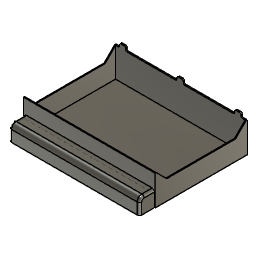
Medium_Drawer_PRINT (Autodesk Fusion 360 design; units mm, degrees)
Autodesk Fusion 360 part; units mm, degrees
sketch "Sketch1" plane through (0, 0, 0) normal (0, 0, 1) x (1, 0, 0)
  line L0 (0, 0) -> (113.9, 0)
  line L1 (113.9, 0) -> (113.9, 80)
  line L2 (113.9, 80) -> (0, 80)
  line L3 (0, 80) -> (0, 0)
  dimension "d1" = 113.9
  dimension "d2" = 80
  constraint horizontal L0
  constraint vertical L1
  constraint horizontal L2
  constraint vertical L3
  constraint coincident L0.start L3.end
  measures "d1" distance of L0.start L0.end
  measures "d2" distance of L0.end L1.end
extrude "Extrude1" add sketch "Sketch1" along normal blind 26.2
shell "Shell1" thickness 0.8 removed faces 1 at (37.9667, 53.3333, 26.2)
ref_plane "WorkPlane1" through (95.5, 40, 13.1) normal (1, 0, 0) x (0, 1, 0)
sketch "Sketch3" plane through (0, 80, 0) normal (0, 1, 0) x (-1, 0, 0)
  line L0 (-113.9, 0) -> (0, 0)
  line L1 (0, 0) -> (0, 26.2)
  line L2 (0, 26.2) -> (-113.9, 26.2)
  line L3 (-113.9, 26.2) -> (-113.9, 0)
  line L4 (-56.95, 26.2) -> (-56.95, 0) construction
  line L5 (-109.65, 27.45) -> (-109.65, 28.45)
  line L6 (-108.4, 29.7) -> (-105.4, 29.7)
  line L7 (-104.15, 28.45) -> (-104.15, 27.45)
  line L8 (-110.9, 26.2) -> (-102.9, 26.2)
  arc A0 (-110.9, 26.2) -> (-109.65, 27.45) centre (-110.9, 27.45) ccw
  arc A1 (-108.4, 29.7) -> (-109.65, 28.45) centre (-108.4, 28.45) ccw
  arc A2 (-104.15, 28.45) -> (-105.4, 29.7) centre (-105.4, 28.45) ccw
  arc A3 (-104.15, 27.45) -> (-102.9, 26.2) centre (-102.9, 27.45) ccw
  arc A4 (-4.25, 28.45) -> (-5.5, 29.7) centre (-5.5, 28.45) ccw
  line L9 (-5.5, 29.7) -> (-8.5, 29.7)
  arc A5 (-11, 26.2) -> (-9.75, 27.45) centre (-11, 27.45) ccw
  arc A6 (-4.25, 27.45) -> (-3, 26.2) centre (-3, 27.45) ccw
  line L10 (-4.25, 27.45) -> (-4.25, 28.45)
  line L11 (-3, 26.2) -> (-11, 26.2)
  arc A7 (-8.5, 29.7) -> (-9.75, 28.45) centre (-8.5, 28.45) ccw
  line L12 (-9.75, 28.45) -> (-9.75, 27.45)
  line L13 (-58.25, 29.7) -> (-55.25, 29.7)
  arc A8 (-58.25, 29.7) -> (-59.5, 28.45) centre (-58.25, 28.45) ccw
  line L14 (-59.5, 27.45) -> (-59.5, 28.45)
  arc A9 (-60.75, 26.2) -> (-59.5, 27.45) centre (-60.75, 27.45) ccw
  arc A10 (-54, 27.45) -> (-52.75, 26.2) centre (-52.75, 27.45) ccw
  line L15 (-60.75, 26.2) -> (-52.75, 26.2)
  line L16 (-54, 28.45) -> (-54, 27.45)
  arc A11 (-54, 28.45) -> (-55.25, 29.7) centre (-55.25, 28.45) ccw
  point P0 (-106.9, 29.7)
  point P1 (-7, 29.7)
  dimension "d18" = 7
  dimension "d19" = 3.5
  dimension "d20" = 5.5
  dimension "d21" = 1.25
  dimension "d62" = 3.5
  dimension "d63" = 5.5
  dimension "d64" = 1.25
  dimension "d65" = 114.3
  dimension "d66" = 44.65
  dimension "d67" = 44.8
  dimension "d68" = 8
  dimension "d69" = 1.25
  dimension "d70" = 3
  dimension "d71" = 1.25
  dimension "d72" = 1.25
  dimension "d73" = 1.25
  dimension "d74" = 3.5
  constraint midpoint L2 L4.start
  constraint perpendicular L2 L4
  constraint coincident L0 L4.end
  constraint horizontal L6
  constraint tangent L6 A1
  constraint tangent L5 A1
  constraint tangent L5 A0
  constraint tangent L6 A2
  constraint tangent L7 A2
  constraint tangent L7 A3
  constraint tangent L8 A3
  constraint tangent L8 A0
  constraint equal A0 A1
  constraint equal A1 A2
  constraint equal A2 A3
  constraint collinear L2 L8
  constraint vertical L7
  constraint vertical L5
  constraint midpoint L6 P0
  constraint symmetric L4 L5.start A6.start
  constraint symmetric L4 L5.end A4.start
  constraint symmetric L4 L6.start A4.end
  constraint symmetric L4 L6.end L9.end
  constraint symmetric L4 L7.start A7.end
  constraint symmetric L4 L7.end A5.end
  constraint symmetric L4 L8.start A6.end
  constraint symmetric L4 L8.end A5.start
  constraint symmetric L4 P0 P1
  constraint symmetric L4 A0 A6
  constraint symmetric L4 A1 A4
  constraint symmetric L4 A2 A7
  constraint symmetric L4 A3 A5
  constraint horizontal L13
  constraint tangent L13 A8
  constraint tangent A8 L14
  constraint tangent L14 A9
  constraint tangent L13 A11
  constraint tangent L16 A11
  constraint tangent A10 L16
  constraint tangent A10 L15
  constraint tangent A9 L15
  constraint equal A8 A9
  constraint equal A8 A11
  constraint equal A10 A11
  constraint vertical L16
  constraint vertical L14
  measures "d18" distance of L3 P0
  measures "d19" distance of L6 L8
  measures "d20" distance of L5 L7
  measures "d21" radius of A0
  measures "d62" distance of L13 L15
  measures "d63" distance of L14 L16
  measures "d64" radius of A9
  measures "d66" distance of L7 L14
  measures "d68" distance of A9.start A10.end
  measures "d69" radius of A10
  measures "d70" distance of L13.start L13.end
  measures "d71" radius of A11
  measures "d72" radius of A9
  measures "d73" radius of A8
  measures "d74" distance of L4.start L13
extrude "Extrude3" add sketch "Sketch3" against normal blind 0.8 contours L2 L5 L6 L7 L8 A0 A1 A2 A3 | L2 A4 L9 A5 A6 L10 L11 A7 L12 | L2 L13 A8 L14 A9 A10 L15 L16 A11
sketch "Sketch4" plane through (113.9, 0, 0) normal (1, 0, 0) x (0, 1, 0)
  line L0 (0, 0) -> (80, 0)
  line L1 (80, 0) -> (80, 26.2)
  line L2 (80, 26.2) -> (0, 26.2)
  line L3 (0, 26.2) -> (0, 0)
  line L4 (0.9071, 26.2) -> (10.1071, 17)
  line L5 (0.9071, 26.2) -> (7.8528, 26.2) construction
  line L6 (10.1071, 17) -> (69.7311, 17)
  line L7 (69.7311, 17) -> (78.9311, 26.2)
  line L8 (78.9311, 26.2) -> (0.9071, 26.2)
  dimension "d24" = 45
  dimension "d25" = 135
  dimension "d26" = 17
  constraint horizontal L5
  constraint coincident L2 L4.start
  constraint horizontal L6
  constraint coincident L2 L7.end
  measures "d24" angle of L4 L5
  measures "d25" angle of L6 L7
  measures "d26" distance of L0 L6
extrude "Extrude4" cut sketch "Sketch4" against normal up to surface (113.9 mm away) contours L2 L4 L6 L7 L8
extrude "Extrude5" add 1 faces at (58.2167, 79.2, 9.2667) along direction (0, -1, 0) blind 0.4
sketch "Sketch5" plane through (0, 0, 0) normal (0, -1, 0) x (1, 0, 0)
  line L0 (0, 0) -> (113.9, 0)
  line L1 (113.9, 0) -> (113.9, 26.2)
  line L2 (113.9, 26.2) -> (0, 26.2)
  line L3 (0, 26.2) -> (0, 0)
  line L4 (0.5, 13.8) -> (113.4, 13.8)
  line L5 (113.4, 13.8) -> (113.4, 13)
  line L6 (113.4, 13) -> (0.5, 13)
  line L7 (0.5, 13) -> (0.5, 13.8)
  dimension "d31" = 0.5
  dimension "d32" = 0.5
  dimension "d33" = 0.8
  dimension "d34" = 13
  constraint horizontal L4
  constraint vertical L5
  constraint horizontal L6
  constraint vertical L7
  measures "d31" distance of L3 L7
  measures "d32" distance of L1 L5
  measures "d33" distance of L4 L6
  measures "d34" distance of L0 L6
extrude "Extrude6" add sketch "Sketch5" along normal blind 13 contours L4 L5 L6 L7
sketch "Sketch6" plane through (0, 0, 13) normal (0, 0, -1) x (1, 0, 0)
  line L0 (0.5, 0) -> (113.4, 0)
  line L1 (113.4, 0) -> (113.4, 13)
  line L2 (113.4, 13) -> (0.5, 13)
  line L3 (0.5, 13) -> (0.5, 0)
  line L4 (0.5, 13) -> (31.3, 13)
  line L5 (31.3, 12.2) -> (0.5, 12.2)
  line L6 (0.5, 12.2) -> (0.5, 13)
  line L7 (31.3, 13) -> (113.4, 13)
  line L8 (31.3, 12.2) -> (113.4, 12.2)
  line L9 (113.4, 12.2) -> (113.4, 13)
  dimension "d37" = 0.8
  constraint horizontal L4
  constraint horizontal L5
  constraint vertical L6
  constraint coincident L2.end L3.start
  constraint coincident L1.end L2.start
  constraint coincident L1 L8.end
  constraint perpendicular L1 L8
  measures "d37" distance of L2.end L5.end
extrude "Extrude7" add sketch "Sketch6" along normal blind 13 contours L1 L2 L3 L4 L5 L6 L7 L8 L9
sketch "Sketch8" plane through (0, 0, 13) normal (0, 0, -1) x (1, 0, 0)
  line L0 (113.4, 12.2) -> (0.5, 12.2)
  line L1 (0.5, 12.2) -> (0.5, 0)
  line L2 (0.5, 0) -> (113.4, 0)
  line L3 (113.4, 0) -> (113.4, 12.2)
  line L4 (1.3, 0) -> (0.5, 0)
  line L5 (0.5, 0) -> (0.5, 12.2)
  line L6 (0.5, 12.2) -> (1.3, 12.2)
  line L7 (1.3, 12.2) -> (1.3, 0)
  line L8 (113.4, 0) -> (112.6, 0)
  line L9 (112.6, 0) -> (112.6, 12.2)
  line L10 (112.6, 12.2) -> (113.4, 12.2)
  line L11 (113.4, 12.2) -> (113.4, 0)
  dimension "d45" = 0.8
  dimension "d46" = 0.8
  constraint horizontal L4
  constraint vertical L5
  constraint horizontal L6
  constraint vertical L7
  constraint coincident L0.end L1.start
  constraint coincident L2 L4.start
  constraint horizontal L8
  constraint vertical L9
  constraint horizontal L10
  constraint vertical L11
  constraint coincident L0 L9.end
  constraint coincident L2.end L3.start
  measures "d45" distance of L9.end L0.start
  measures "d46" distance of L0.end L6.end
extrude "Extrude9" add sketch "Sketch8" along normal blind 13 contours L0 L2 L3 L8 L9 L10 L11 | L0 L1 L2 L4 L5 L6 L7
fillet "Fillet2" radius 4 2 edges at (56.95, -12.2, 13) (56.95, -13, 13.8)
chamfer "Chamfer1" distance 3 angle 45 1 edges at (56.95, 0, 13)
fillet "Fillet4" radius 2 6 edges at (1.3, -12.2, 4.5) (1.3, -11.0284, 11.8284) (1.3, -5.6, 13) (0.5, -4.5, 13.8) (0.5, -11.8284, 12.6284) (0.5, -13, 4.9)
fillet "Fillet5" radius 2 3 edges at (112.6, -5.6, 13) (112.6, -11.0284, 11.8284) (112.6, -12.2, 4.5)
fillet "Fillet6" radius 2 3 edges at (113.4, -4.5, 13.8) (113.4, -11.8284, 12.6284) (113.4, -13, 4.9)
equation "d1 = 114.7 mm - 0.8 mm"
